Autodesk Fusion 360 part; units mm, degrees
(part 2 of 2)
sketch "Sketch24" plane through (0, 0, 0) normal (0, 0, 1) x (1, 0, 0)
  line L0 (-150, 200) -> (150, 200)
  line L1 (150, 200) -> (150, 192)
  line L2 (150, 192) -> (-150, 192)
  line L3 (-150, 192) -> (-150, 200)
  line L4 (-150, 200) -> (-147, 200)
  line L5 (-147, 200) -> (-147, 225)
  line L6 (-147, 225) -> (-150, 225)
  line L7 (-150, 225) -> (-150, 200)
  line L8 (-145.6957, 200) -> (-142.6957, 200)
  line L9 (-142.6957, 225) -> (-145.6957, 225)
  line L10 (-145.6957, 225) -> (-145.6957, 200)
  line L11 (-142.6957, 200) -> (-142.6957, 225)
  line L12 (-141.3913, 200) -> (-138.3913, 200)
  line L13 (-138.3913, 225) -> (-141.3913, 225)
  line L14 (-141.3913, 225) -> (-141.3913, 200)
  line L15 (-138.3913, 200) -> (-138.3913, 225)
  line L16 (-137.087, 200) -> (-134.087, 200)
  line L17 (-134.087, 225) -> (-137.087, 225)
  line L18 (-137.087, 225) -> (-137.087, 200)
  line L19 (-134.087, 200) -> (-134.087, 225)
  line L20 (-132.7826, 200) -> (-129.7826, 200)
  line L21 (-129.7826, 225) -> (-132.7826, 225)
  line L22 (-132.7826, 225) -> (-132.7826, 200)
  line L23 (-129.7826, 200) -> (-129.7826, 225)
  line L24 (-128.4783, 200) -> (-125.4783, 200)
  line L25 (-125.4783, 225) -> (-128.4783, 225)
  line L26 (-128.4783, 225) -> (-128.4783, 200)
  line L27 (-125.4783, 200) -> (-125.4783, 225)
  line L28 (-124.1739, 200) -> (-121.1739, 200)
  line L29 (-121.1739, 225) -> (-124.1739, 225)
  line L30 (-124.1739, 225) -> (-124.1739, 200)
  line L31 (-121.1739, 200) -> (-121.1739, 225)
  line L32 (-119.8696, 200) -> (-116.8696, 200)
  line L33 (-116.8696, 225) -> (-119.8696, 225)
  line L34 (-119.8696, 225) -> (-119.8696, 200)
  line L35 (-116.8696, 200) -> (-116.8696, 225)
  line L36 (-115.5652, 200) -> (-112.5652, 200)
  line L37 (-112.5652, 225) -> (-115.5652, 225)
  line L38 (-115.5652, 225) -> (-115.5652, 200)
  line L39 (-112.5652, 200) -> (-112.5652, 225)
  line L40 (-111.2609, 200) -> (-108.2609, 200)
  line L41 (-108.2609, 225) -> (-111.2609, 225)
  line L42 (-111.2609, 225) -> (-111.2609, 200)
  line L43 (-108.2609, 200) -> (-108.2609, 225)
  line L44 (-106.9565, 200) -> (-103.9565, 200)
  line L45 (-103.9565, 225) -> (-106.9565, 225)
  line L46 (-106.9565, 225) -> (-106.9565, 200)
  line L47 (-103.9565, 200) -> (-103.9565, 225)
  line L48 (-102.6522, 200) -> (-99.6522, 200)
  line L49 (-99.6522, 225) -> (-102.6522, 225)
  line L50 (-102.6522, 225) -> (-102.6522, 200)
  line L51 (-99.6522, 200) -> (-99.6522, 225)
  line L52 (-98.3478, 200) -> (-95.3478, 200)
  line L53 (-95.3478, 225) -> (-98.3478, 225)
  line L54 (-98.3478, 225) -> (-98.3478, 200)
  line L55 (-95.3478, 200) -> (-95.3478, 225)
  line L56 (-94.0435, 200) -> (-91.0435, 200)
  line L57 (-91.0435, 225) -> (-94.0435, 225)
  line L58 (-94.0435, 225) -> (-94.0435, 200)
  line L59 (-91.0435, 200) -> (-91.0435, 225)
  line L60 (-89.7391, 200) -> (-86.7391, 200)
  line L61 (-86.7391, 225) -> (-89.7391, 225)
  line L62 (-89.7391, 225) -> (-89.7391, 200)
  line L63 (-86.7391, 200) -> (-86.7391, 225)
  line L64 (-85.4348, 200) -> (-82.4348, 200)
  line L65 (-82.4348, 225) -> (-85.4348, 225)
  line L66 (-85.4348, 225) -> (-85.4348, 200)
  line L67 (-82.4348, 200) -> (-82.4348, 225)
  line L68 (-81.1304, 200) -> (-78.1304, 200)
  line L69 (-78.1304, 225) -> (-81.1304, 225)
  line L70 (-81.1304, 225) -> (-81.1304, 200)
  line L71 (-78.1304, 200) -> (-78.1304, 225)
  line L72 (-76.8261, 200) -> (-73.8261, 200)
  line L73 (-73.8261, 225) -> (-76.8261, 225)
  line L74 (-76.8261, 225) -> (-76.8261, 200)
  line L75 (-73.8261, 200) -> (-73.8261, 225)
  line L76 (-72.5217, 200) -> (-69.5217, 200)
  line L77 (-69.5217, 225) -> (-72.5217, 225)
  line L78 (-72.5217, 225) -> (-72.5217, 200)
  line L79 (-69.5217, 200) -> (-69.5217, 225)
  line L80 (-68.2174, 200) -> (-65.2174, 200)
  line L81 (-65.2174, 225) -> (-68.2174, 225)
  line L82 (-68.2174, 225) -> (-68.2174, 200)
  line L83 (-65.2174, 200) -> (-65.2174, 225)
  line L84 (-63.913, 200) -> (-60.913, 200)
  line L85 (-60.913, 225) -> (-63.913, 225)
  line L86 (-63.913, 225) -> (-63.913, 200)
  line L87 (-60.913, 200) -> (-60.913, 225)
  line L88 (-59.6087, 200) -> (-56.6087, 200)
  line L89 (-56.6087, 225) -> (-59.6087, 225)
  line L90 (-59.6087, 225) -> (-59.6087, 200)
  line L91 (-56.6087, 200) -> (-56.6087, 225)
  line L92 (-55.3043, 200) -> (-52.3043, 200)
  line L93 (-52.3043, 225) -> (-55.3043, 225)
  line L94 (-55.3043, 225) -> (-55.3043, 200)
  line L95 (-52.3043, 200) -> (-52.3043, 225)
  line L96 (-51, 200) -> (-48, 200)
  line L97 (-48, 225) -> (-51, 225)
  line L98 (-51, 225) -> (-51, 200)
  line L99 (-48, 200) -> (-48, 225)
  line L100 (-46.6957, 200) -> (-43.6957, 200)
  line L101 (-43.6957, 225) -> (-46.6957, 225)
  line L102 (-46.6957, 225) -> (-46.6957, 200)
  line L103 (-43.6957, 200) -> (-43.6957, 225)
  line L104 (-42.3913, 200) -> (-39.3913, 200)
  line L105 (-39.3913, 225) -> (-42.3913, 225)
  line L106 (-42.3913, 225) -> (-42.3913, 200)
  line L107 (-39.3913, 200) -> (-39.3913, 225)
  line L108 (-38.087, 200) -> (-35.087, 200)
  line L109 (-35.087, 225) -> (-38.087, 225)
  line L110 (-38.087, 225) -> (-38.087, 200)
  line L111 (-35.087, 200) -> (-35.087, 225)
  line L112 (-33.7826, 200) -> (-30.7826, 200)
  line L113 (-30.7826, 225) -> (-33.7826, 225)
  line L114 (-33.7826, 225) -> (-33.7826, 200)
  line L115 (-30.7826, 200) -> (-30.7826, 225)
  line L116 (-29.4783, 200) -> (-26.4783, 200)
  line L117 (-26.4783, 225) -> (-29.4783, 225)
  line L118 (-29.4783, 225) -> (-29.4783, 200)
  line L119 (-26.4783, 200) -> (-26.4783, 225)
  line L120 (-25.1739, 200) -> (-22.1739, 200)
  line L121 (-22.1739, 225) -> (-25.1739, 225)
  line L122 (-25.1739, 225) -> (-25.1739, 200)
  line L123 (-22.1739, 200) -> (-22.1739, 225)
  line L124 (-20.8696, 200) -> (-17.8696, 200)
  line L125 (-17.8696, 225) -> (-20.8696, 225)
  line L126 (-20.8696, 225) -> (-20.8696, 200)
  line L127 (-17.8696, 200) -> (-17.8696, 225)
  line L128 (-16.5652, 200) -> (-13.5652, 200)
  line L129 (-13.5652, 225) -> (-16.5652, 225)
  line L130 (-16.5652, 225) -> (-16.5652, 200)
  line L131 (-13.5652, 200) -> (-13.5652, 225)
  line L132 (-12.2609, 200) -> (-9.2609, 200)
  line L133 (-9.2609, 225) -> (-12.2609, 225)
  line L134 (-12.2609, 225) -> (-12.2609, 200)
  line L135 (-9.2609, 200) -> (-9.2609, 225)
  line L136 (-7.9565, 200) -> (-4.9565, 200)
  line L137 (-4.9565, 225) -> (-7.9565, 225)
  line L138 (-7.9565, 225) -> (-7.9565, 200)
  line L139 (-4.9565, 200) -> (-4.9565, 225)
  line L140 (-3.6522, 200) -> (-0.6522, 200)
  line L141 (-0.6522, 225) -> (-3.6522, 225)
  line L142 (-3.6522, 225) -> (-3.6522, 200)
  line L143 (-0.6522, 200) -> (-0.6522, 225)
  line L144 (0.6522, 200) -> (3.6522, 200)
  line L145 (3.6522, 225) -> (0.6522, 225)
  line L146 (0.6522, 225) -> (0.6522, 200)
  line L147 (3.6522, 200) -> (3.6522, 225)
  line L148 (4.9565, 200) -> (7.9565, 200)
  line L149 (7.9565, 225) -> (4.9565, 225)
  line L150 (4.9565, 225) -> (4.9565, 200)
  line L151 (7.9565, 200) -> (7.9565, 225)
  line L152 (9.2609, 200) -> (12.2609, 200)
  line L153 (12.2609, 225) -> (9.2609, 225)
  line L154 (9.2609, 225) -> (9.2609, 200)
  line L155 (12.2609, 200) -> (12.2609, 225)
  line L156 (13.5652, 200) -> (16.5652, 200)
  line L157 (16.5652, 225) -> (13.5652, 225)
  line L158 (13.5652, 225) -> (13.5652, 200)
  line L159 (16.5652, 200) -> (16.5652, 225)
  line L160 (17.8696, 200) -> (20.8696, 200)
  line L161 (20.8696, 225) -> (17.8696, 225)
  line L162 (17.8696, 225) -> (17.8696, 200)
  line L163 (20.8696, 200) -> (20.8696, 225)
  line L164 (22.1739, 200) -> (25.1739, 200)
  line L165 (25.1739, 225) -> (22.1739, 225)
  line L166 (22.1739, 225) -> (22.1739, 200)
  line L167 (25.1739, 200) -> (25.1739, 225)
  line L168 (26.4783, 200) -> (29.4783, 200)
  line L169 (29.4783, 225) -> (26.4783, 225)
  line L170 (26.4783, 225) -> (26.4783, 200)
  line L171 (29.4783, 200) -> (29.4783, 225)
  line L172 (30.7826, 200) -> (33.7826, 200)
  line L173 (33.7826, 225) -> (30.7826, 225)
  line L174 (30.7826, 225) -> (30.7826, 200)
  line L175 (33.7826, 200) -> (33.7826, 225)
  line L176 (35.087, 200) -> (38.087, 200)
  line L177 (38.087, 225) -> (35.087, 225)
  line L178 (35.087, 225) -> (35.087, 200)
  line L179 (38.087, 200) -> (38.087, 225)
  line L180 (39.3913, 200) -> (42.3913, 200)
  line L181 (42.3913, 225) -> (39.3913, 225)
  line L182 (39.3913, 225) -> (39.3913, 200)
  line L183 (42.3913, 200) -> (42.3913, 225)
  line L184 (43.6957, 200) -> (46.6957, 200)
  line L185 (46.6957, 225) -> (43.6957, 225)
  line L186 (43.6957, 225) -> (43.6957, 200)
  line L187 (46.6957, 200) -> (46.6957, 225)
  line L188 (48, 200) -> (51, 200)
  line L189 (51, 225) -> (48, 225)
  line L190 (48, 225) -> (48, 200)
  line L191 (51, 200) -> (51, 225)
  line L192 (52.3043, 200) -> (55.3043, 200)
  line L193 (55.3043, 225) -> (52.3043, 225)
  line L194 (52.3043, 225) -> (52.3043, 200)
  line L195 (55.3043, 200) -> (55.3043, 225)
  line L196 (56.6087, 200) -> (59.6087, 200)
  line L197 (59.6087, 225) -> (56.6087, 225)
  line L198 (56.6087, 225) -> (56.6087, 200)
  line L199 (59.6087, 200) -> (59.6087, 225)
  line L200 (60.913, 200) -> (63.913, 200)
  line L201 (63.913, 225) -> (60.913, 225)
  line L202 (60.913, 225) -> (60.913, 200)
  line L203 (63.913, 200) -> (63.913, 225)
  line L204 (65.2174, 200) -> (68.2174, 200)
  line L205 (68.2174, 225) -> (65.2174, 225)
  line L206 (65.2174, 225) -> (65.2174, 200)
  line L207 (68.2174, 200) -> (68.2174, 225)
  line L208 (69.5217, 200) -> (72.5217, 200)
  line L209 (72.5217, 225) -> (69.5217, 225)
  line L210 (69.5217, 225) -> (69.5217, 200)
  line L211 (72.5217, 200) -> (72.5217, 225)
  line L212 (73.8261, 200) -> (76.8261, 200)
  line L213 (76.8261, 225) -> (73.8261, 225)
  line L214 (73.8261, 225) -> (73.8261, 200)
  line L215 (76.8261, 200) -> (76.8261, 225)
  line L216 (78.1304, 200) -> (81.1304, 200)
  line L217 (81.1304, 225) -> (78.1304, 225)
  line L218 (78.1304, 225) -> (78.1304, 200)
  line L219 (81.1304, 200) -> (81.1304, 225)
  line L220 (82.4348, 200) -> (85.4348, 200)
  line L221 (85.4348, 225) -> (82.4348, 225)
  line L222 (82.4348, 225) -> (82.4348, 200)
  line L223 (85.4348, 200) -> (85.4348, 225)
  line L224 (86.7391, 200) -> (89.7391, 200)
  line L225 (89.7391, 225) -> (86.7391, 225)
  line L226 (86.7391, 225) -> (86.7391, 200)
  line L227 (89.7391, 200) -> (89.7391, 225)
  line L228 (91.0435, 200) -> (94.0435, 200)
  line L229 (94.0435, 225) -> (91.0435, 225)
  line L230 (91.0435, 225) -> (91.0435, 200)
  line L231 (94.0435, 200) -> (94.0435, 225)
  line L232 (95.3478, 200) -> (98.3478, 200)
  line L233 (98.3478, 225) -> (95.3478, 225)
  line L234 (95.3478, 225) -> (95.3478, 200)
  line L235 (98.3478, 200) -> (98.3478, 225)
  line L236 (99.6522, 200) -> (102.6522, 200)
  line L237 (102.6522, 225) -> (99.6522, 225)
  line L238 (99.6522, 225) -> (99.6522, 200)
  line L239 (102.6522, 200) -> (102.6522, 225)
  line L240 (103.9565, 200) -> (106.9565, 200)
  line L241 (106.9565, 225) -> (103.9565, 225)
  line L242 (103.9565, 225) -> (103.9565, 200)
  line L243 (106.9565, 200) -> (106.9565, 225)
  line L244 (108.2609, 200) -> (111.2609, 200)
  line L245 (111.2609, 225) -> (108.2609, 225)
  line L246 (108.2609, 225) -> (108.2609, 200)
  line L247 (111.2609, 200) -> (111.2609, 225)
  line L248 (112.5652, 200) -> (115.5652, 200)
  line L249 (115.5652, 225) -> (112.5652, 225)
  line L250 (112.5652, 225) -> (112.5652, 200)
  line L251 (115.5652, 200) -> (115.5652, 225)
  line L252 (116.8696, 200) -> (119.8696, 200)
  line L253 (119.8696, 225) -> (116.8696, 225)
  line L254 (116.8696, 225) -> (116.8696, 200)
  line L255 (119.8696, 200) -> (119.8696, 225)
  line L256 (121.1739, 200) -> (124.1739, 200)
  line L257 (124.1739, 225) -> (121.1739, 225)
  line L258 (121.1739, 225) -> (121.1739, 200)
  line L259 (124.1739, 200) -> (124.1739, 225)
  line L260 (125.4783, 200) -> (128.4783, 200)
  line L261 (128.4783, 225) -> (125.4783, 225)
  line L262 (125.4783, 225) -> (125.4783, 200)
  line L263 (128.4783, 200) -> (128.4783, 225)
  line L264 (129.7826, 200) -> (132.7826, 200)
  line L265 (132.7826, 225) -> (129.7826, 225)
  line L266 (129.7826, 225) -> (129.7826, 200)
  line L267 (132.7826, 200) -> (132.7826, 225)
  line L268 (134.087, 200) -> (137.087, 200)
  line L269 (137.087, 225) -> (134.087, 225)
  line L270 (134.087, 225) -> (134.087, 200)
  line L271 (137.087, 200) -> (137.087, 225)
  line L272 (138.3913, 200) -> (141.3913, 200)
  line L273 (141.3913, 225) -> (138.3913, 225)
  line L274 (138.3913, 225) -> (138.3913, 200)
  line L275 (141.3913, 200) -> (141.3913, 225)
  line L276 (142.6957, 200) -> (145.6957, 200)
  line L277 (145.6957, 225) -> (142.6957, 225)
  line L278 (142.6957, 225) -> (142.6957, 200)
  line L279 (145.6957, 200) -> (145.6957, 225)
  line L280 (147, 200) -> (150, 200)
  line L281 (150, 225) -> (147, 225)
  line L282 (147, 225) -> (147, 200)
  line L283 (150, 200) -> (150, 225)
  dimension "d299" = 300
  dimension "d300" = 8
  dimension "d304" = 3
  dimension "d305" = 25
  dimension "d308" = 297
  dimension "d309" = 0
  constraint horizontal L0
  constraint vertical L1
  constraint horizontal L2
  constraint vertical L3
  constraint horizontal L4
  constraint vertical L5
  constraint horizontal L6
  constraint vertical L7
  measures "d299" distance of L0.start L0.end
  measures "d300" distance of L0.start L2.end
  measures "d304" distance of L0.start L4.end
  measures "d305" distance of L0.start L6.end
extrude "Extrude31" add sketch "Sketch24" along normal blind 1 separate body makes body 10
extrude "Extrude32" add sketch "Sketch24" along normal blind 4.75 contours L0 L1 L2 L3 L4 L8 L12 L16 L20 L24 L28 L32 L36 L40 L44 L48 L52 L56 L60 L64 L68 L72 L76 L80 L84 L88 L92 L96 L100 L104 L108 L112 L116 L120 L124 L128 L132 L136 L140 L144 L148 L152 L156 L160 L164 L168 L172 L176 L180 L184 L188 L192 L196 L200 L204 L208 L212 L216 L220 L224 L228 L232 L236 L240 L244 L248 L252 L256 L260 L264 L268 L272 L276 L280 bodies 10
sketch "Sketch25" plane through (0, 0, 0) normal (0, 1, 0) x (1, 0, 0)
equation "d5 = collarDepth"
equation "d10 = collarDepth * 2"
equation "collarDepth = 20 mm" comment "depth of the spindle collar"
equation "d25 = -collarDepth + 2 mm"
equation "d41 = d40 / 3.5"
equation "d43 = ( 7.75 / 2 ) * 1 mm"
equation "d44 = ( 7.75 / 2 ) * 1 mm"
equation "d45 = d46"
equation "d51 = collarDepth"
equation "d138 = d152"
equation "d140 = d152"
equation "d142 = d152"
equation "d156 = d157 / 5"
equation "d158 = d156"
equation "d159 = d156"
equation "d160 = d159"
equation "d161 = ( 7.8 / 2 ) * 1 mm"
equation "d162 = ( 7.8 / 2 ) * 1 mm"
equation "d163 = ( 7.8 / 2 ) * 1 mm"
equation "d164 = ( 7.8 / 2 ) * 1 mm"
equation "d167 = d157 / 2"
equation "d168 = d167"
equation "d169 = ( 7.8 / 2 ) * 1 mm"
equation "d170 = ( 7.8 / 2 ) * 1 mm"
equation "d172 = d171 / 3.5"
equation "d173 = d172"
equation "d174 = ( 7.8 / 2 ) * 1 mm"
equation "d175 = ( 7.8 / 2 ) * 1 mm"
equation "d181 = d180 / 3.5"
equation "d182 = d181"
equation "d183 = ( 7.8 / 2 ) * 1 mm"
equation "d184 = ( 7.8 / 2 ) * 1 mm"
equation "d193 = -collarDepth"
equation "d206 = magnetSize"
equation "d207 = d208"
equation "d208 = magnetSize"
equation "d209 = magnetSize"
equation "d210 = magnetSize"
equation "d211 = magnetSize"
equation "d212 = magnetSize"
equation "d213 = magnetSize"
equation "d222 = magnetSize"
equation "d240 = ( d239 - d238 ) / 2"
equation "d242 = d251"
equation "d249 = ( d248 - d247 ) / 2"
equation "d251 = 71 mm - d253"
equation "d256 = ( d252 - d255 ) / 2"
equation "d269 = d268"
equation "d270 = d268"
equation "d271 = d268"
equation "magnetSize = 5.01 mm"
equation "brushLength = 25 mm"
equation "brushWidth = 3 mm"
equation "brushwidthGap = 2 mm"
equation "d304 = brushWidth"
equation "d305 = brushLength"
equation "d308 = 300 mm - brushWidth"
equation "d310 = bristleThickness"
equation "bristleThickness = 1 mm"
named bodies: "Top Shoe", "Spindle Holder 1", "Spindle Holder 2", "Hose Holder Rear", "Hose Holder Front", "Shoe Dock", "Bottom Shoe", "Shoe Brush"
